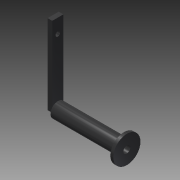
# Autodesk Inventor part: pedal
Saved by Autodesk Inventor 2015 (Build 190159000, 159)
## iProperties
Created: 2022-11-04
Part Number: pedal
Material: Generic
Document SubType Name: Modeling
Designer: Pavel Brodský
Density: 1 g/cm^3
Appearance: Default
Author: Pavel Brodský
Autodesk Inventor part; units mm, degrees
ref_plane "YZ Plane" through (0, 0, 0) normal (1, 0, 0) x (0, 1, 0)
ref_plane "XZ Plane" through (0, 0, 0) normal (0, 1, 0) x (-1, 0, 0)
ref_plane "XY Plane" through (0, 0, 0) normal (0, 0, 1) x (1, 0, 0)
sketch "Náčrt1" plane through (0, 0, 0) normal (1, 0, 0) x (0, 1, 0)
  circle A0 centre (0, 0) radius 23
  circle A1 centre (0, 0) radius 6
  circle A2 centre (0, 0) radius 12.5
  dimension "d0" = 46
  dimension "d1" = 12
  dimension "d4" = 25
  constraints: 3 centre point, 3 coincident
  measures "d0" diameter of A0
  measures "d1" diameter of A1
  measures "d4" diameter of A2
extrude "Vysunutí1" add sketch "Náčrt1" along normal blind 5 contours A0 | A2
extrude "Vysunutí2" add sketch "Náčrt1" against normal blind 112 contours A2
sketch "Náčrt2" plane through (-112, 0, 0) normal (-1, 0, 0) x (0, 0, 1)
  circle A0 centre (0, 0) radius 6 projected
  line L0 (0, -9.5) -> (135, -9.5)
  line L1 (135, -9.5) -> (135, 9.5)
  line L2 (135, 9.5) -> (0, 9.5)
  line L3 (0, 9.5) -> (0, -9.5)
  circle A1 centre (111, 0) radius 4
  point P0 (135, 0)
  dimension "d8" = 19
  dimension "d9" = 135
  dimension "d10" = 8
  dimension "d11" = 24
  constraints: 8 end point, 2 midpoint, 2 parallel, 1 centre point, 1 coincident, 1 horizontal, 1 horizontal alignment, 1 perpendicular
  measures "d8" distance between parallel lines of L2 L0
  measures "d9" distance of L1.end L2.end
  measures "d10" diameter of A1
  measures "d11" distance from line of L1 A1.centre
extrude "Vysunutí3" add sketch "Náčrt2" along normal blind 8 contours A0 L3 | A0 L3 L2 L1 L0 picked at (1.5637, 1.247)
